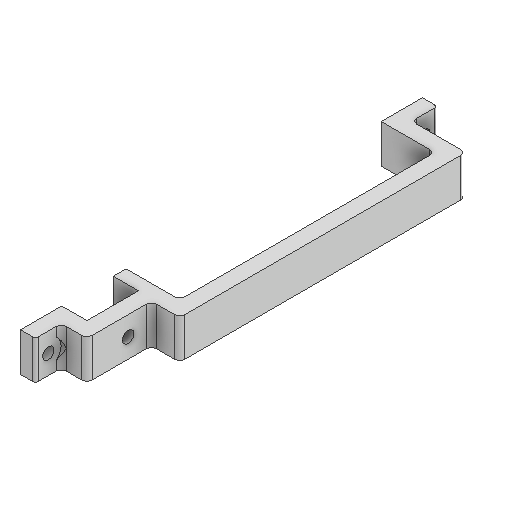
# Autodesk Inventor part: 3DP_PLA_Power_Brick_Mounting_Clamp_REVB
Saved by Autodesk Inventor 2027 (Build 310192060, 192F)
## iProperties
Created: 2026-03-01
Part Number: 3DP_PLA_Power_Brick_Mounting_Clamp_REVB
Material: Generic
Document SubType Name: Modeling
Designer: User
Density: 1 g/cm^3
Appearance: Default
Author: User
Autodesk Inventor part; units mm, degrees
ref_plane "YZ Plane" through (0, 0, 0) normal (1, 0, 0) x (0, 1, 0)
ref_plane "XZ Plane" through (0, 0, 0) normal (0, 1, 0) x (-1, 0, 0)
ref_plane "XY Plane" through (0, 0, 0) normal (0, 0, 1) x (1, 0, 0)
sketch "Sketch1" plane through (0, 0, 0) normal (0, 1, 0) x (-1, 0, 0)
  line L0 (10, 10) -> (-10, 10)
  line L1 (-10, 10) -> (-10, -15)
  line L2 (10, -15) -> (10, 10)
  line L3 (21, -15) -> (21, -114)
  line L4 (21, -114) -> (-21, -114)
  line L5 (-21, -114) -> (-21, -15)
  line L6 (-21, -15) -> (-10, -15)
  line L7 (10, -15) -> (21, -15)
  line L8 (-27, -9) -> (-27, -120)
  line L9 (-27, -120) -> (27, -120)
  line L10 (27, -120) -> (27, -9)
  line L11 (27, -9) -> (16, -9)
  line L12 (16, -9) -> (16, 16)
  line L13 (16, 16) -> (-16, 16)
  line L14 (-16, 16) -> (-16, -9)
  line L15 (-16, -9) -> (-27, -9)
  line L16 (-10, -15) -> (-8, -15)
  line L17 (-8, -15) -> (10, -15)
  line L18 (10, -10) -> (-10, -10)
  line L19 (0, 16) -> (0, 10)
  line L20 (0, -10) -> (0, -15)
  line L21 (0, -114) -> (0, -120)
  line L22 (0, -120) -> (0, -130)
  line L23 (0, -130) -> (-6, -130)
  line L24 (-6, -130) -> (-6, -120)
  line L25 (0, 16) -> (0, 26)
  line L26 (0, 26) -> (-6, 26)
  line L27 (-6, 26) -> (-6, 16)
  point P0 (0, 0)
  dimension "d0" = 20
  dimension "d2" = 10
  dimension "d3" = 10
  dimension "d4" = 99
  dimension "d5" = 42
  dimension "d6" = 11
  dimension "d7" = 25
  dimension "d8" = 25
  dimension "d9" = 6
  dimension "d10" = 6
  dimension "d11" = 10
  dimension "d12" = 10
  dimension "d13" = 6
  constraints: 56 end point, 11 perpendicular, 8 parallel, 6 point on line, 4 midpoint, 3 horizontal, 2 vertical, 1 collinear, 7 other
  measures "d0" distance between parallel lines of L1 L2
  measures "d2" distance from line of point (0, 0) L1
  measures "d3" distance from line of point (0, 0) L0
  measures "d4" distance of L3.start L3.end
  measures "d5" distance of L3.end L4.end
  measures "d6" distance between parallel lines of L2 L3
  measures "d7" distance between parallel lines of L0 L7
  measures "d8" distance between parallel lines of L0 L6
  measures "d9" distance between parallel lines of L5 L8
  measures "d10" distance between parallel lines of L22 L24
  measures "d11" distance between parallel lines of L9 L23
  measures "d12" distance of L19.start L25.end
  measures "d13" distance of L25.end L26.end
extrude "Extrusion1" add sketch "Sketch1" along normal blind 15 contours L0 L1 L6 L5 L4 L21 L9 L8 L15 L14 L13 L19 | L13 L27 L26 L25 | L20 L17 L16 L1 L18 | L22 L23 L24 L9
sketch "Sketch2" plane through (0, 0, 10) normal (-1, 0, 0) x (0, 0, 1)
  line L0 (-178, 34) -> (31, 34)
  line L1 (31, 34) -> (31, -20)
  line L2 (31, -20) -> (-178, -20)
  line L3 (-178, -20) -> (-178, 34)
  point P0 (-10, 0)
  constraints: 8 end point, 2 parallel, 1 horizontal, 1 perpendicular
extrude "Extrusion2" cut sketch "Sketch2" against normal blind 0.2
sketch "Sketch3" plane through (10, 0, -10) normal (-1, 0, 0) x (0, 0, 1)
  line L0 (0, 0) -> (20, 0) projected
  line L1 (20, 0) -> (20, 15) projected
  line L2 (0, 15) -> (20, 15) projected
  line L3 (0, 0) -> (0, 15) projected
  point P0 (10, 0)
  point P1 (10, 7.5)
  dimension "d18" = 15
  dimension "d19" = 7.5
  dimension "d20" = 10
  measures "d18" distance between parallel lines of L2 L0
  measures "d19" distance from line of L2 point (10, 7.5)
  measures "d20" distance from line of L1 point (10, 7.5)
hole "Hole1" at (10, 7.5, 0) direction (1, 0, 0) diameter 4.5 end through all
sketch "Sketch4" plane through (6, 0, 26) normal (1, 0, 0) x (0, 0, -1)
  line L0 (0, 0) -> (10, 0) projected
  line L1 (10, 0) -> (10, 15) projected
  line L2 (0, 15) -> (10, 15) projected
  line L3 (0, 0) -> (0, 15) projected
  line L4 (146, 0) -> (156, 0) projected
  line L5 (156, 0) -> (156, 15) projected
  line L6 (146, 15) -> (156, 15) projected
  line L7 (146, 0) -> (146, 15) projected
  point P0 (26, 0)
  point P1 (5, 7.5)
  point P2 (151, 7.5)
  dimension "d28" = 7.5
  dimension "d29" = 5
  dimension "d30" = 5
  dimension "d31" = 7.5
  measures "d28" distance from line of L4 point (151, 7.5)
  measures "d29" distance from line of L5 point (151, 7.5)
  measures "d30" distance from line of L3 point (5, 7.5)
  measures "d31" distance from line of L0 point (5, 7.5)
hole "Hole2" at (6, 7.5, 21) at (6, 7.5, -125) direction (-1, 0, 0) diameter 4.5 end through all
fillet "Fillet1" radius 2 8 edges at (16, 7.5, 16) (16, 7.5, -9) (27, 7.5, -9) (27, 7.5, -120) (21, 7.5, -114) (21, 7.5, -15) (6, 7.5, -120) (6, 7.5, 16)
fillet "Fillet2" radius 1 2 edges at (6, 7.5, 26) (6, 7.5, -130)
sketch "Sketch5" plane through (6, 0, 18) normal (1, 0, 0) x (0, 0, -1)
  circle A0 centre (-3, 7.5) radius 2.25 projected
  circle A1 centre (143, 7.5) radius 2.25 projected
  line L0 (138, 0) -> (138, 15) projected
  line L1 (2, 15) -> (2, 0) projected
  circle A2 centre (-3, 7.5) radius 5
  circle A3 centre (143, 7.5) radius 5
  point P0 (18, 0)
  constraints: 2 centre point, 2 coincident, 1 tangent
extrude "Extrusion3" cut sketch "Sketch5" along normal blind 15
equation "\"d2\" = 0.5 * d0"
equation "\"d3\" = 0.5 * d1"
equation "\"d6\" = -0.5 * d0 + 0.5 * d5"
equation "\"d8\" = d7"
equation "\"d19\" = 0.5 * d18"
equation "\"d1\" = 20"
body "Solid1"
